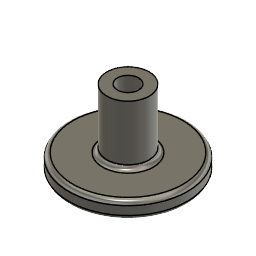
ToF_spacer_front (Autodesk Fusion 360 design; units mm, degrees)
part number: 2026-07-29-11-21-42-864
Autodesk Fusion 360 part; units mm, degrees
sketch "Sketch1" plane through (0, 0, 0) normal (0, 1, 0) x (1, 0, 0)
  circle A0 centre (0, 0) radius 1.25
  circle A1 centre (0, 0) radius 7
  dimension "d1" = 2.5
  dimension "d2" = 14
  constraint coincident A0.centre A1.centre
  constraint concentric A0 A1
  measures "d1" diameter of A0
  measures "d2" diameter of A1
extrude "Extrude1" add sketch "Sketch1" along normal blind 2 makes body 1
extrude "Extrude2" add sketch "Sketch1" along normal blind 2 separate body makes body 2
sketch "Sketch2" plane through (0, 2, 0) normal (0, 1, 0) x (-1, 0, 0)
  circle A0 centre (0, 0) radius 1.25
  circle A1 centre (0, 0) radius 7
  circle A2 centre (0, 0) radius 2.5
  dimension "d7" = 5
  constraint concentric A0 A2
  measures "d7" diameter of A2
extrude "Extrude3" add sketch "Sketch2" along normal blind 7 contours A2 bodies 1 2
fillet "Fillet1" radius 0.5 1 edges at (2.3308, 2, 0.904) 1 faces at (6.9913, 1.3333, 0.3489) on bodies 1
